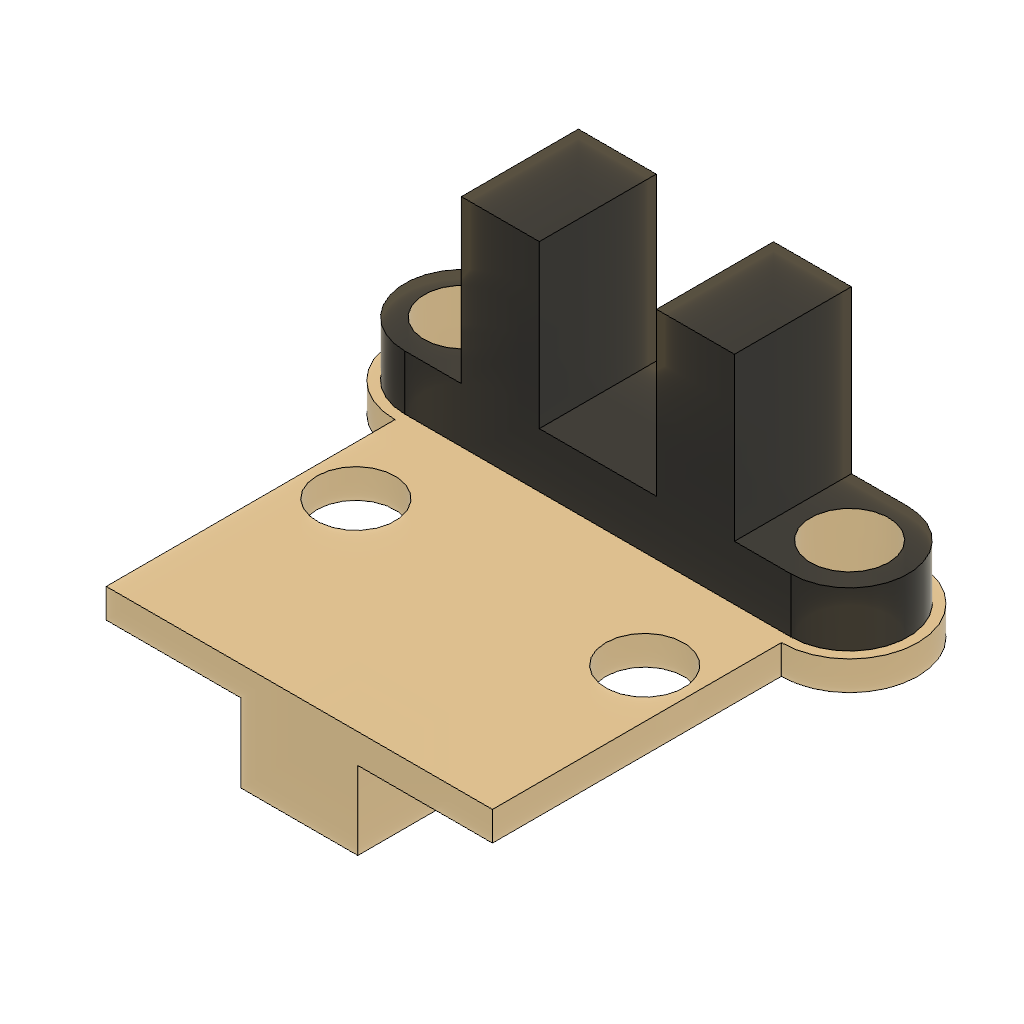
Encoder_HC020K (Autodesk Fusion 360 design; units mm, degrees)
Autodesk Fusion 360 part; units mm, degrees
sketch "Boceto1" plane through (0, 0, 0) normal (0, 1, 0) x (1, 0, 0)
  line L0 (9.9, 10.9) -> (-9.9, 10.9)
  line L1 (-9.9, -10.9) -> (9.9, -10.9)
  line L2 (9.9, -10.9) -> (9.9, 3.9)
  line L3 (9.9, 10.9) -> (-9.9, -10.9) construction
  line L4 (-9.9, 10.9) -> (9.9, -10.9) construction
  circle A0 centre (9.9, 7.4) radius 2
  line L5 (0, -2.845) -> (0, 2.6261) construction
  line L6 (-1.6752, 0) -> (2.3909, 0) construction
  circle A1 centre (-9.9, 7.4) radius 2
  line L7 (-9.9, 3.9) -> (-9.9, -10.9)
  arc A2 (-9.9, 10.9) -> (-9.9, 3.9) centre (-9.9, 7.4) ccw
  arc A3 (9.9, 3.9) -> (9.9, 10.9) centre (9.9, 7.4) ccw
  dimension "d1" = 19.8
  dimension "d2" = 21.8
  dimension "d3" = 7
  dimension "d4" = 3.5
  dimension "d5" = 4
  dimension "d6" = 19.8
  dimension "d7" = 14.8
  constraint horizontal L0
  constraint parallel L0 L1
  constraint coincident L3 origin
  constraint coincident L4 origin
  constraint coincident L2 A0.centre
  constraint concentric A0 A3
  constraint vertical L5
  constraint perpendicular L5 L6
  constraint symmetric L5 A2 A3
  constraint symmetric A0 L5 A1
  measures "d1" distance of L1.start L1.end
  measures "d2" distance of L0.end L1.start
  measures "d3" diameter of A3
  measures "d4" distance of L0.start A0.centre
  measures "d5" diameter of A0
  measures "d6" distance of A0.centre A1.centre
  measures "d7" distance of L1.start L7.start
extrude "Extruir1" add sketch "Boceto1" along normal blind 1.5
sketch "Boceto2" plane through (0, 1.5, 0) normal (0, 1, 0) x (-1, 0, 0)
  circle A0 centre (9.9, -7.4) radius 2
  circle A1 centre (-9.9, -7.4) radius 2
  arc A2 (-9.9, -3.9) -> (-9.9, -10.9) centre (-9.9, -7.4) ccw
  line L0 (-9.9, -10.9) -> (9.9, -10.9)
  arc A3 (9.9, -10.9) -> (9.9, -3.9) centre (9.9, -7.4) ccw
  line L1 (9.9, -3.9) -> (9.9, 10.9)
  line L2 (9.9, 10.9) -> (-9.9, 10.9)
  line L3 (-9.9, 10.9) -> (-9.9, -3.9)
  circle A4 centre (9.9, -7.4) radius 2
  circle A5 centre (-9.9, -7.4) radius 2
  line L4 (9.9, -10.4) -> (-9.9, -10.4)
  line L5 (9.9, -4.4) -> (-9.9, -4.4)
  arc A6 (9.9, -10.4) -> (9.9, -4.4) centre (9.9, -7.4) ccw
  arc A7 (-9.9, -4.4) -> (-9.9, -10.4) centre (-9.9, -7.4) ccw
  dimension "d10" = 6
  dimension "d11" = 6
  constraint concentric A0 A4
  constraint concentric A4 A6
  constraint concentric A1 A5
  constraint concentric A5 A7
  constraint tangent L4 A7
  constraint horizontal L4
  constraint tangent L5 A7
  constraint parallel L4 L5
  measures "d10" diameter of A6
  measures "d11" diameter of A7
extrude "Extruir2" add sketch "Boceto2" along normal blind 2.8 contours L4 L5 A6 A7
sketch "Boceto3" plane through (0, 4.3, 0) normal (0, 1, 0) x (-1, 0, 0)
  circle A0 centre (-9.9, -7.4) radius 2
  circle A1 centre (9.9, -7.4) radius 2
  arc A2 (9.9, -10.4) -> (9.9, -4.4) centre (9.9, -7.4) ccw
  line L0 (9.9, -4.4) -> (-9.9, -4.4)
  arc A3 (-9.9, -4.4) -> (-9.9, -10.4) centre (-9.9, -7.4) ccw
  line L1 (-9.9, -10.4) -> (9.9, -10.4)
  line L2 (0, 0) -> (0, -11.5742) construction
  line L3 (9.9, -7.4) -> (-9.9, -7.4) construction
  line L4 (7, -4.4) -> (-7, -4.4)
  line L5 (-7, -4.4) -> (-7, -10.4)
  line L6 (-7, -10.4) -> (7, -10.4)
  line L7 (7, -10.4) -> (7, -4.4)
  line L8 (7, -4.4) -> (-7, -10.4) construction
  line L9 (-7, -4.4) -> (7, -10.4) construction
  line L10 (-7, -10.4) -> (-3, -10.4)
  line L11 (-3, -10.4) -> (-3, -4.4)
  line L12 (-3, -4.4) -> (-7, -4.4)
  line L13 (-7, -4.4) -> (-7, -10.4)
  line L14 (7, -10.4) -> (3, -10.4)
  line L15 (3, -10.4) -> (3, -4.4)
  line L16 (3, -4.4) -> (7, -4.4)
  line L17 (7, -4.4) -> (7, -10.4)
  point P0 (0, -7.4)
  dimension "d14" = 14
  dimension "d15" = 6
  dimension "d16" = 4
  dimension "d17" = 4
  constraint coincident L2.start origin
  constraint perpendicular L1 L2
  constraint coincident A1.centre A2.centre
  constraint coincident A0.centre A3.centre
  constraint horizontal L4
  constraint perpendicular L4 L5
  constraint parallel L4 L6
  constraint parallel L5 L7
  constraint coincident L8 P0
  constraint coincident L9 P0
  constraint midpoint L3 P0
  constraint horizontal L10
  constraint vertical L11
  constraint horizontal L12
  constraint vertical L13
  constraint horizontal L14
  constraint vertical L15
  constraint horizontal L16
  constraint vertical L17
  measures "d14" distance of L5.end L6.end
  measures "d15" distance of L4.end L5.end
  measures "d16" distance of L5.end L10.end
  measures "d17" distance of L6.end L14.end
extrude "Extruir3" add sketch "Boceto3" along normal blind 8.3 contours L0 L1 L4 L6 L7 L14 L15 L16 L17 | L0 L1 L4 L5 L6 L10 L11 L12 L13
sketch "Boceto4" plane through (0, 0, 0) normal (0, -1, 0) x (1, 0, 0)
  circle A0 centre (-9.9, -7.4) radius 2
  circle A1 centre (9.9, -7.4) radius 2
  arc A2 (9.9, -10.9) -> (9.9, -3.9) centre (9.9, -7.4) ccw
  line L0 (9.9, -3.9) -> (9.9, 10.9)
  line L1 (9.9, 10.9) -> (-9.9, 10.9)
  line L2 (-9.9, 10.9) -> (-9.9, -3.9)
  arc A3 (-9.9, -3.9) -> (-9.9, -10.9) centre (-9.9, -7.4) ccw
  line L3 (-9.9, -10.9) -> (9.9, -10.9)
  line L4 (-3, 10.9) -> (-3, 4.9)
  line L5 (-3, 4.9) -> (3, 4.9)
  line L6 (3, 4.9) -> (3, 10.9)
  line L7 (0, 10.9) -> (-3, 4.9) construction
  line L8 (0, 10.9) -> (3, 4.9) construction
  line L9 (-3, 10.9) -> (3, 10.9)
  dimension "d20" = 6
  constraint parallel L4 L6
  constraint midpoint L1 L7.start
  constraint coincident L1 L4.start
  constraint coincident L1 L6.end
  constraint perpendicular L6 L9
  measures "d20" distance of L4.end L5.end
extrude "Extruir4" add sketch "Boceto4" along normal blind 4 contours L1 L4 L5 L6 L9
sketch "Boceto5" plane through (0, 0, 0) normal (0, -1, 0) x (1, 0, 0)
  line L0 (3, 10.9) -> (3, 4.9)
  line L1 (3, 4.9) -> (-3, 4.9)
  line L2 (-3, 4.9) -> (-3, 10.9)
  line L3 (-3, 10.9) -> (-9.9, 10.9)
  line L4 (-9.9, 10.9) -> (-9.9, -3.9)
  arc A0 (-9.9, -3.9) -> (-9.9, -10.9) centre (-9.9, -7.4) ccw
  line L5 (-9.9, -10.9) -> (9.9, -10.9)
  arc A1 (9.9, -10.9) -> (9.9, -3.9) centre (9.9, -7.4) ccw
  line L6 (9.9, -3.9) -> (9.9, 10.9)
  line L7 (9.9, 10.9) -> (3, 10.9)
  circle A2 centre (9.9, -7.4) radius 2
  circle A3 centre (-9.9, -7.4) radius 2
  circle A4 centre (7.4, 0.6) radius 2
  line L8 (0, 1.3993) -> (0, -2.7753) construction
  circle A5 centre (-7.4, 0.6) radius 2
  dimension "d24" = 4
  dimension "d25" = 8
  dimension "d26" = 2.5
  constraint vertical L8
  constraint symmetric A4 L8 A5
  measures "d24" diameter of A4
  measures "d25" vertical distance of A1.centre A4.centre
  measures "d26" horizontal distance of A1.centre A4.centre
extrude "Extruir5" cut sketch "Boceto5" against normal blind 2 contours A4 | A5
equation "d3 = ( 3.5 * 2 ) * 1 mm"
